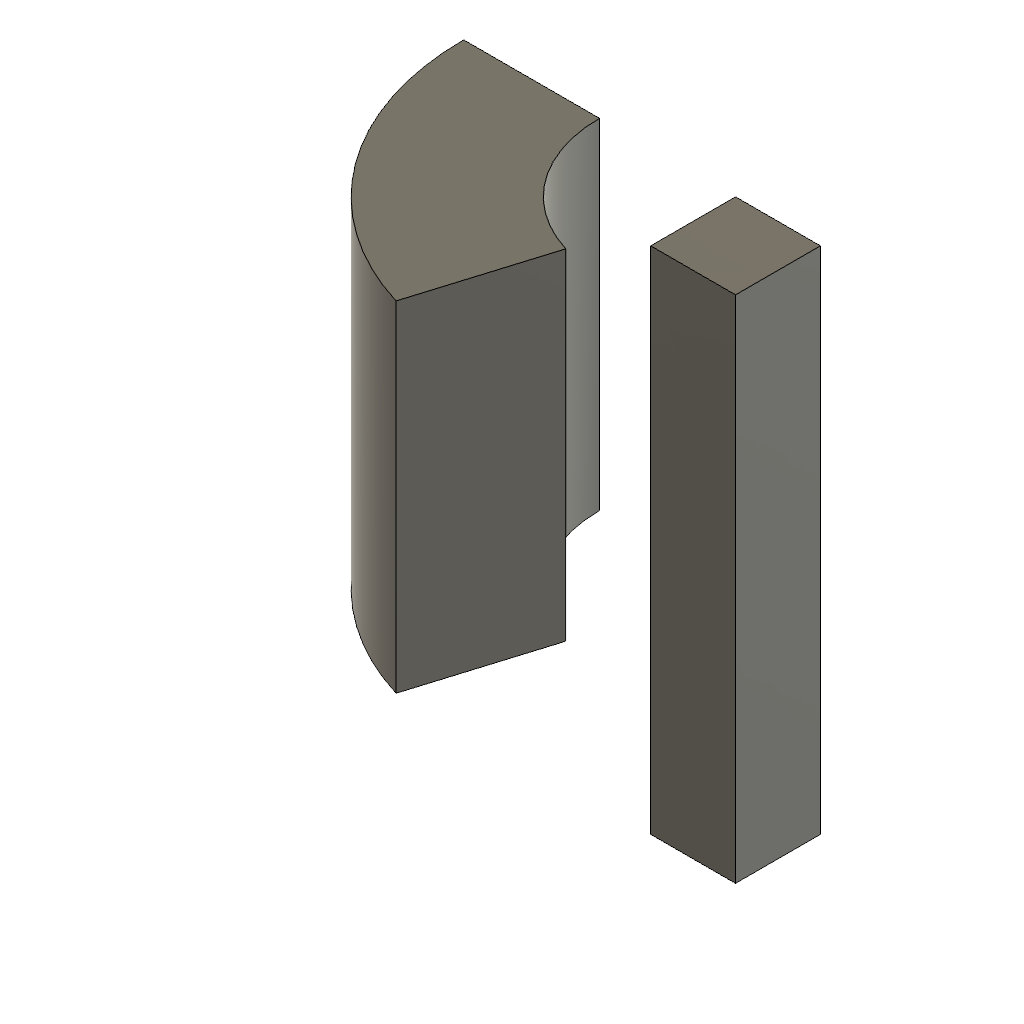
brep_edge (Autodesk Fusion 360 design; units mm, degrees)
part number: 2026-10-20-23-11-57-765
Autodesk Fusion 360 part; units mm, degrees
sketch "AxisSupportSketch" plane through (0, 0, 0) normal (0, 0, 1) x (1, 0, 0)
  line L0 (0, 0) -> (5, 0)
  line L1 (5, 0) -> (5, 30)
  line L2 (5, 30) -> (0, 30)
  line L3 (0, 30) -> (0, 0)
extrude "AxisSeedExtrusion" add sketch "AxisSupportSketch" along normal blind 5 makes body 1
sketch "AxisProbeProfile" plane through (0, 0, 0) normal (0, 0, 1) x (1, 0, 0)
  line L0 (-8, 10) -> (-8, 30)
  line L1 (-8, 30) -> (-16, 30)
  line L2 (-16, 30) -> (-16, 10)
  line L3 (-16, 10) -> (-8, 10)
revolve "ProbeAxisRevolve" add sketch "AxisProbeProfile" angle 73 about axis through (0, 30, 0) along (0, 1, 0) separate body makes body 2
named bodies: "AxisSeedBody"
